711002_P01_ELECTRICAL-POWER-UNIT-FRONT-PLATE_CAD (Autodesk Fusion 360 design; units mm, degrees)
description: ELECTRICAL - POWER UNIT - FRONT PLATE | Điện - hộp nguồn - mặt trước | P01
part number: 711002
Autodesk Fusion 360 part; units mm, degrees
sketch "OUTLINE AND CUT-OUTS - FRONT" plane through (0, 0, 0) normal (0, 0, 1) x (1, 0, 0) in component "711002 ELECTRICAL - POWER UNIT - FRONT PLATE"
  line L0 (0, 0) -> (320, 0)
  line L1 (320, 0) -> (320, 284)
  line L2 (320, 284) -> (0, 284)
  line L3 (0, 284) -> (0, 0)
  line L4 (65.2, 158.5) -> (98.8, 158.5)
  line L5 (98.8, 158.5) -> (98.8, 225.5)
  line L6 (98.8, 225.5) -> (65.2, 225.5)
  line L7 (65.2, 225.5) -> (65.2, 158.5)
  circle A0 centre (82, 143.6) radius 1.9
  line L8 (167.55, 182.3) -> (182.45, 182.3)
  line L9 (182.45, 182.3) -> (182.45, 201.7)
  line L10 (182.45, 201.7) -> (167.55, 201.7)
  line L11 (167.55, 201.7) -> (167.55, 182.3)
  circle A1 centre (82, 240.4) radius 1.9
  line L12 (191.55, 182.3) -> (206.45, 182.3)
  line L13 (206.45, 182.3) -> (206.45, 201.7)
  line L14 (206.45, 201.7) -> (191.55, 201.7)
  line L15 (191.55, 201.7) -> (191.55, 182.3)
  line L16 (247.5, 169.5) -> (266.5, 169.5)
  line L17 (266.5, 169.5) -> (266.5, 214.5)
  line L18 (266.5, 214.5) -> (247.5, 214.5)
  line L19 (247.5, 214.5) -> (247.5, 169.5)
  line L20 (40, 35) -> (80, 35)
  line L21 (80, 35) -> (80, 39)
  line L22 (80, 39) -> (40, 39)
  line L23 (40, 39) -> (40, 35)
  line L24 (90, 35) -> (130, 35)
  line L25 (130, 35) -> (130, 39)
  line L26 (130, 39) -> (90, 39)
  line L27 (90, 39) -> (90, 35)
  line L28 (140, 35) -> (180, 35)
  line L29 (180, 35) -> (180, 39)
  line L30 (180, 39) -> (140, 39)
  line L31 (140, 39) -> (140, 35)
  line L32 (190, 35) -> (230, 35)
  line L33 (230, 35) -> (230, 39)
  line L34 (230, 39) -> (190, 39)
  line L35 (190, 39) -> (190, 35)
  line L36 (240, 35) -> (280, 35)
  line L37 (280, 35) -> (280, 39)
  line L38 (280, 39) -> (240, 39)
  line L39 (240, 39) -> (240, 35)
  line L40 (40, 130) -> (80, 130)
  line L41 (80, 130) -> (80, 134)
  line L42 (80, 134) -> (40, 134)
  line L43 (40, 134) -> (40, 130)
  line L44 (90, 130) -> (130, 130)
  line L45 (130, 130) -> (130, 134)
  line L46 (130, 134) -> (90, 134)
  line L47 (90, 134) -> (90, 130)
  line L48 (140, 130) -> (180, 130)
  line L49 (180, 130) -> (180, 134)
  line L50 (180, 134) -> (140, 134)
  line L51 (140, 134) -> (140, 130)
  line L52 (190, 130) -> (230, 130)
  line L53 (230, 130) -> (230, 134)
  line L54 (230, 134) -> (190, 134)
  line L55 (190, 134) -> (190, 130)
  line L56 (240, 130) -> (280, 130)
  line L57 (280, 130) -> (280, 134)
  line L58 (280, 134) -> (240, 134)
  line L59 (240, 134) -> (240, 130)
  circle A2 centre (42, 22) radius 2.25
  circle A3 centre (278, 22) radius 2.25
  circle A4 centre (42, 262) radius 2.25
  circle A5 centre (278, 262) radius 2.25
  dimension "d314" = 320
  dimension "d315" = 284
  dimension "d316" = 33.6
  dimension "d317" = 67
  dimension "d318" = 65.2
  dimension "d319" = 158.5
  dimension "d320" = 3.8
  dimension "d321" = 82
  dimension "d322" = 143.6
  dimension "d323" = 14.9
  dimension "d324" = 19.4
  dimension "d325" = 167.55
  dimension "d326" = 182.3
  dimension "d327" = 3.8
  dimension "d328" = 82
  dimension "d329" = 240.4
  dimension "d330" = 14.9
  dimension "d331" = 19.4
  dimension "d332" = 191.55
  dimension "d333" = 182.3
  dimension "d334" = 19
  dimension "d335" = 45
  dimension "d336" = 247.5
  dimension "d337" = 169.5
  dimension "d338" = 40
  dimension "d339" = 4
  dimension "d340" = 40
  dimension "d341" = 35
  dimension "d342" = 40
  dimension "d343" = 4
  dimension "d344" = 90
  dimension "d345" = 35
  dimension "d346" = 40
  dimension "d347" = 4
  dimension "d348" = 140
  dimension "d349" = 35
  dimension "d350" = 40
  dimension "d351" = 4
  dimension "d352" = 190
  dimension "d353" = 35
  dimension "d354" = 40
  dimension "d355" = 4
  dimension "d356" = 240
  dimension "d357" = 35
  dimension "d358" = 40
  dimension "d359" = 4
  dimension "d360" = 40
  dimension "d361" = 130
  dimension "d362" = 40
  dimension "d363" = 4
  dimension "d364" = 90
  dimension "d365" = 130
  dimension "d366" = 40
  dimension "d367" = 4
  dimension "d368" = 140
  dimension "d369" = 130
  dimension "d370" = 40
  dimension "d371" = 4
  dimension "d372" = 190
  dimension "d373" = 130
  dimension "d374" = 40
  dimension "d375" = 4
  dimension "d376" = 240
  dimension "d377" = 130
  dimension "d378" = 4.5
  dimension "d379" = 42
  dimension "d380" = 22
  dimension "d381" = 4.5
  dimension "d382" = 278
  dimension "d383" = 22
  dimension "d384" = 4.5
  dimension "d385" = 42
  dimension "d386" = 262
  dimension "d387" = 4.5
  dimension "d388" = 278
  dimension "d389" = 262
  constraint horizontal L0
  constraint vertical L1
  constraint horizontal L2
  constraint vertical L3
  constraint vertical L0.start L3.end
  constraint horizontal L0.start L3.end
  constraint horizontal L4
  constraint vertical L5
  constraint horizontal L6
  constraint vertical L7
  constraint horizontal L8
  constraint vertical L9
  constraint horizontal L10
  constraint vertical L11
  constraint horizontal L12
  constraint vertical L13
  constraint horizontal L14
  constraint vertical L15
  constraint horizontal L16
  constraint vertical L17
  constraint horizontal L18
  constraint vertical L19
  constraint horizontal L20
  constraint vertical L21
  constraint horizontal L22
  constraint vertical L23
  constraint horizontal L24
  constraint vertical L25
  constraint horizontal L26
  constraint vertical L27
  constraint horizontal L28
  constraint vertical L29
  constraint horizontal L30
  constraint vertical L31
  constraint horizontal L32
  constraint vertical L33
  constraint horizontal L34
  constraint vertical L35
  constraint horizontal L36
  constraint vertical L37
  constraint horizontal L38
  constraint vertical L39
  constraint horizontal L40
  constraint vertical L41
  constraint horizontal L42
  constraint vertical L43
  constraint horizontal L44
  constraint vertical L45
  constraint horizontal L46
  constraint vertical L47
  constraint horizontal L48
  constraint vertical L49
  constraint horizontal L50
  constraint vertical L51
  constraint horizontal L52
  constraint vertical L53
  constraint horizontal L54
  constraint vertical L55
  constraint horizontal L56
  constraint vertical L57
  constraint horizontal L58
  constraint vertical L59
  measures "d314" horizontal distance of L0.start L0.end
  measures "d315" vertical distance of L0.start L2.end
  measures "d316" horizontal distance of L4.start L4.end
  measures "d317" vertical distance of L4.start L6.end
  measures "d318" horizontal distance of L0.start L4.start
  measures "d319" vertical distance of L0.start L4.start
  measures "d320" diameter of A0
  measures "d321" horizontal distance of L0.start A0.centre
  measures "d322" vertical distance of L0.start A0.centre
  measures "d323" horizontal distance of L8.start L8.end
  measures "d324" vertical distance of L8.start L10.end
  measures "d325" horizontal distance of L0.start L8.start
  measures "d326" vertical distance of L0.start L8.start
  measures "d327" diameter of A1
  measures "d328" horizontal distance of L0.start A1.centre
  measures "d329" vertical distance of L0.start A1.centre
  measures "d330" horizontal distance of L12.start L12.end
  measures "d331" vertical distance of L12.start L14.end
  measures "d332" horizontal distance of L0.start L12.start
  measures "d333" vertical distance of L0.start L12.start
  measures "d334" horizontal distance of L16.start L16.end
  measures "d335" vertical distance of L16.start L18.end
  measures "d336" horizontal distance of L0.start L16.start
  measures "d337" vertical distance of L0.start L16.start
  measures "d338" horizontal distance of L20.start L20.end
  measures "d339" vertical distance of L20.start L22.end
  measures "d340" horizontal distance of L0.start L20.start
  measures "d341" vertical distance of L0.start L20.start
  measures "d342" horizontal distance of L24.start L24.end
  measures "d343" vertical distance of L24.start L26.end
  measures "d344" horizontal distance of L0.start L24.start
  measures "d345" vertical distance of L0.start L24.start
  measures "d346" horizontal distance of L28.start L28.end
  measures "d347" vertical distance of L28.start L30.end
  measures "d348" horizontal distance of L0.start L28.start
  measures "d349" vertical distance of L0.start L28.start
  measures "d350" horizontal distance of L32.start L32.end
  measures "d351" vertical distance of L32.start L34.end
  measures "d352" horizontal distance of L0.start L32.start
  measures "d353" vertical distance of L0.start L32.start
  measures "d354" horizontal distance of L36.start L36.end
  measures "d355" vertical distance of L36.start L38.end
  measures "d356" horizontal distance of L0.start L36.start
  measures "d357" vertical distance of L0.start L36.start
  measures "d358" horizontal distance of L40.start L40.end
  measures "d359" vertical distance of L40.start L42.end
  measures "d360" horizontal distance of L0.start L40.start
  measures "d361" vertical distance of L0.start L40.start
  measures "d362" horizontal distance of L44.start L44.end
  measures "d363" vertical distance of L44.start L46.end
  measures "d364" horizontal distance of L0.start L44.start
  measures "d365" vertical distance of L0.start L44.start
  measures "d366" horizontal distance of L48.start L48.end
  measures "d367" vertical distance of L48.start L50.end
  measures "d368" horizontal distance of L0.start L48.start
  measures "d369" vertical distance of L0.start L48.start
  measures "d370" horizontal distance of L52.start L52.end
  measures "d371" vertical distance of L52.start L54.end
  measures "d372" horizontal distance of L0.start L52.start
  measures "d373" vertical distance of L0.start L52.start
  measures "d374" horizontal distance of L56.start L56.end
  measures "d375" vertical distance of L56.start L58.end
  measures "d376" horizontal distance of L0.start L56.start
  measures "d377" vertical distance of L0.start L56.start
  measures "d378" diameter of A2
  measures "d379" horizontal distance of L0.start A2.centre
  measures "d380" vertical distance of L0.start A2.centre
  measures "d381" diameter of A3
  measures "d382" horizontal distance of L0.start A3.centre
  measures "d383" vertical distance of L0.start A3.centre
  measures "d384" diameter of A4
  measures "d385" horizontal distance of L0.start A4.centre
  measures "d386" vertical distance of L0.start A4.centre
  measures "d387" diameter of A5
  measures "d388" horizontal distance of L0.start A5.centre
  measures "d389" vertical distance of L0.start A5.centre
extrude "EXTRUDE - PLATE FRONT" add sketch "OUTLINE AND CUT-OUTS - FRONT" along normal blind 1.5 in component "711002 ELECTRICAL - POWER UNIT - FRONT PLATE"
component "711002 ELECTRICAL - POWER UNIT - FRONT PLATE" placed x (1, 0, 0) y (0, 1, 0) z (0, 0, 1) at (0, 0, 0)
equation "t = 1.5 mm" comment "PROPOSED: 5052-H32 aluminium 1.5 mm, black anodised AA20 (D-67)"
equation "w = 320.0 mm" comment "CALCULATION: the unit's width 296 + 2 x (4 mm clear + 8 mm over the felt): the plate covers the cut-out's felt edge all round (route model pu_w, pu_clr, plate_ov)"
equation "h = 284.0 mm" comment "CALCULATION: the unit's height 260 + 2 x (4 + 8) (route model pu_h, pu_clr, plate_ov)"
equation "box_a = 73 mm" comment "HOLD: opening for an 86-type back box mouth; the UTEN code and its box set it (H-ELE-04)"
equation "box_zc = edge_off + 195 mm" comment "ASSUMPTION: 86-plate openings' centre height: 195 above the unit's bottom (Z 1065, the unit's centre + 65)"
equation "box_x1 = edge_off + 70 mm" comment "ASSUMPTION: socket opening centre: 70 from the unit's left side (the box mouth 11.5 mm clear of the body's 22 mm left lip)"
equation "box_x2 = edge_off + 175 mm" comment "ASSUMPTION: LAN opening centre: 175 from the unit's left side (32 mm between the two box mouths)"
equation "din_w = 19 mm" comment "SOURCE: breaker window: 1 module + 1 (Eaton FAZ-NA is 17.7 mm per pole, D-133)"
equation "din_h = 45 mm" comment "SOURCE: DIN 43880 front height 45 mm"
equation "din_x = edge_off + 245 mm" comment "ASSUMPTION: breaker window centre: 245 from the unit's left side, 41 mm from the keystone openings, 19.5 mm clear of the body's 22 mm right lip"
equation "din_zc = dev_zc" comment "ASSUMPTION: breaker window centre height, level with the devices"
equation "vent_l = 40 mm" comment "ASSUMPTION: vent slot length"
equation "vent_w = 4 mm" comment "ASSUMPTION: vent slot width"
equation "vent_n = 5" comment "ASSUMPTION: vent slots per row (two rows: bottom and top)"
equation "vent_p = 50 mm" comment "ASSUMPTION: vent slot pitch"
equation "vent_z1 = edge_off + 25 mm" comment "ASSUMPTION: bottom vent row centre: 25 above the unit's bottom, just above the body's 22 mm lip"
equation "vent_z2 = edge_off + 120 mm" comment "ASSUMPTION: top vent row centre: 120 above the unit's bottom, 4.7 mm under the GFCI receptacle's strap (D-133)"
equation "screw_d = 4.5 mm" comment "ASSUMPTION: M4 screw clearance hole"
equation "screw_x = edge_off + 30 mm" comment "CALCULATION: screw centre: on the body's clinch nuts, 30 from the unit's sides (clinch_x)"
equation "screw_y = edge_off + 10 mm" comment "CALCULATION: screw centre: on the body's clinch nuts, 10 from the unit's top and bottom (clinch_y; 22 from the plate's edge, C09)"
equation "edge_off = 12.0 mm" comment "CALCULATION: the unit's edge from the plate's edge: 4 mm clear + 8 mm over the felt; every opening is placed from the unit's edge"
equation "dev_zc = edge_off + 180 mm" comment "ASSUMPTION: the devices' centre height: 180 above the unit's bottom; the GFCI receptacle's 106.7 mm strap runs 126.7 to 233.3, 4.7 mm clear of the top vent row and of the body's 22 mm top lip (D-133)"
equation "gfci_w = 33.6 mm" comment "HOLD: GFCI receptacle's decorator opening width: the face 33.3 (1.31 in) + 0.3; the picked receptacle's drawing sets it (D-133)"
equation "gfci_h = 67 mm" comment "HOLD: decorator opening height: the face 66.7 (2.625 in) + 0.3 (D-133)"
equation "gfci_x = edge_off + 70 mm" comment "ASSUMPTION: GFCI opening centre: 70 from the unit's left side; its 43.7 mm strap is 26 mm clear of the body's 22 mm left lip"
equation "gfci_sp = 96.8 mm" comment "SOURCE: the two 6-32 plate screws' spacing on a decorator device's strap: 3-13/16 in"
equation "gfci_sd = 3.8 mm" comment "ASSUMPTION: 6-32 clearance hole (normal fit)"
equation "ks_w = 14.9 mm" comment "HOLD: keystone jack opening width (the common 0.585 x 0.760 in snap-in opening; the picked jack sets it, D-133)"
equation "ks_h = 19.4 mm" comment "HOLD: keystone jack opening height"
equation "ks_x = edge_off + 175 mm" comment "ASSUMPTION: LAN: the two keystone openings' centre, 175 from the unit's left side"
equation "ks_p = 24 mm" comment "ASSUMPTION: the two keystone openings' pitch: side by side, the jacks' 16.5 mm bodies 7.5 mm apart"
equation "d314 = ( w ) - ( 0 mm )"
equation "d315 = ( h ) - ( 0 mm )"
equation "d316 = ( gfci_x + gfci_w / 2 ) - ( gfci_x - gfci_w / 2 )"
equation "d317 = ( dev_zc + gfci_h / 2 ) - ( dev_zc - gfci_h / 2 )"
equation "d318 = abs(gfci_x - gfci_w / 2)"
equation "d319 = abs(dev_zc - gfci_h / 2)"
equation "d320 = gfci_sd"
equation "d321 = abs(gfci_x)"
equation "d322 = abs(dev_zc - gfci_sp / 2)"
equation "d323 = ( ( ks_x - ks_p / 2 ) + ks_w / 2 ) - ( ( ks_x - ks_p / 2 ) - ks_w / 2 )"
equation "d324 = ( dev_zc + ks_h / 2 ) - ( dev_zc - ks_h / 2 )"
equation "d325 = abs(( ks_x - ks_p / 2 ) - ks_w / 2)"
equation "d326 = abs(dev_zc - ks_h / 2)"
equation "d327 = gfci_sd"
equation "d328 = abs(gfci_x)"
equation "d329 = abs(dev_zc + gfci_sp / 2)"
equation "d330 = ( ( ks_x + ks_p / 2 ) + ks_w / 2 ) - ( ( ks_x + ks_p / 2 ) - ks_w / 2 )"
equation "d331 = ( dev_zc + ks_h / 2 ) - ( dev_zc - ks_h / 2 )"
equation "d332 = abs(( ks_x + ks_p / 2 ) - ks_w / 2)"
equation "d333 = abs(dev_zc - ks_h / 2)"
equation "d334 = ( din_x + din_w / 2 ) - ( din_x - din_w / 2 )"
equation "d335 = ( din_zc + din_h / 2 ) - ( din_zc - din_h / 2 )"
equation "d336 = abs(din_x - din_w / 2)"
equation "d337 = abs(din_zc - din_h / 2)"
equation "d338 = ( ( w / 2 + ( 0 - ( vent_n - 1 ) / 2 ) * vent_p ) + vent_l / 2 ) - ( ( w / 2 + ( 0 - ( vent_n - 1 ) / 2 ) * vent_p ) - vent_l / 2 )"
equation "d339 = ( ( vent_z1 ) + vent_w / 2 ) - ( ( vent_z1 ) - vent_w / 2 )"
equation "d340 = abs(( w / 2 + ( 0 - ( vent_n - 1 ) / 2 ) * vent_p ) - vent_l / 2)"
equation "d341 = abs(( vent_z1 ) - vent_w / 2)"
equation "d342 = ( ( w / 2 + ( 1 - ( vent_n - 1 ) / 2 ) * vent_p ) + vent_l / 2 ) - ( ( w / 2 + ( 1 - ( vent_n - 1 ) / 2 ) * vent_p ) - vent_l / 2 )"
equation "d343 = ( ( vent_z1 ) + vent_w / 2 ) - ( ( vent_z1 ) - vent_w / 2 )"
equation "d344 = abs(( w / 2 + ( 1 - ( vent_n - 1 ) / 2 ) * vent_p ) - vent_l / 2)"
equation "d345 = abs(( vent_z1 ) - vent_w / 2)"
equation "d346 = ( ( w / 2 + ( 2 - ( vent_n - 1 ) / 2 ) * vent_p ) + vent_l / 2 ) - ( ( w / 2 + ( 2 - ( vent_n - 1 ) / 2 ) * vent_p ) - vent_l / 2 )"
equation "d347 = ( ( vent_z1 ) + vent_w / 2 ) - ( ( vent_z1 ) - vent_w / 2 )"
equation "d348 = abs(( w / 2 + ( 2 - ( vent_n - 1 ) / 2 ) * vent_p ) - vent_l / 2)"
equation "d349 = abs(( vent_z1 ) - vent_w / 2)"
equation "d350 = ( ( w / 2 + ( 3 - ( vent_n - 1 ) / 2 ) * vent_p ) + vent_l / 2 ) - ( ( w / 2 + ( 3 - ( vent_n - 1 ) / 2 ) * vent_p ) - vent_l / 2 )"
equation "d351 = ( ( vent_z1 ) + vent_w / 2 ) - ( ( vent_z1 ) - vent_w / 2 )"
equation "d352 = abs(( w / 2 + ( 3 - ( vent_n - 1 ) / 2 ) * vent_p ) - vent_l / 2)"
equation "d353 = abs(( vent_z1 ) - vent_w / 2)"
equation "d354 = ( ( w / 2 + ( 4 - ( vent_n - 1 ) / 2 ) * vent_p ) + vent_l / 2 ) - ( ( w / 2 + ( 4 - ( vent_n - 1 ) / 2 ) * vent_p ) - vent_l / 2 )"
equation "d355 = ( ( vent_z1 ) + vent_w / 2 ) - ( ( vent_z1 ) - vent_w / 2 )"
equation "d356 = abs(( w / 2 + ( 4 - ( vent_n - 1 ) / 2 ) * vent_p ) - vent_l / 2)"
equation "d357 = abs(( vent_z1 ) - vent_w / 2)"
equation "d358 = ( ( w / 2 + ( 0 - ( vent_n - 1 ) / 2 ) * vent_p ) + vent_l / 2 ) - ( ( w / 2 + ( 0 - ( vent_n - 1 ) / 2 ) * vent_p ) - vent_l / 2 )"
equation "d359 = ( ( vent_z2 ) + vent_w / 2 ) - ( ( vent_z2 ) - vent_w / 2 )"
equation "d360 = abs(( w / 2 + ( 0 - ( vent_n - 1 ) / 2 ) * vent_p ) - vent_l / 2)"
equation "d361 = abs(( vent_z2 ) - vent_w / 2)"
equation "d362 = ( ( w / 2 + ( 1 - ( vent_n - 1 ) / 2 ) * vent_p ) + vent_l / 2 ) - ( ( w / 2 + ( 1 - ( vent_n - 1 ) / 2 ) * vent_p ) - vent_l / 2 )"
equation "d363 = ( ( vent_z2 ) + vent_w / 2 ) - ( ( vent_z2 ) - vent_w / 2 )"
equation "d364 = abs(( w / 2 + ( 1 - ( vent_n - 1 ) / 2 ) * vent_p ) - vent_l / 2)"
equation "d365 = abs(( vent_z2 ) - vent_w / 2)"
equation "d366 = ( ( w / 2 + ( 2 - ( vent_n - 1 ) / 2 ) * vent_p ) + vent_l / 2 ) - ( ( w / 2 + ( 2 - ( vent_n - 1 ) / 2 ) * vent_p ) - vent_l / 2 )"
equation "d367 = ( ( vent_z2 ) + vent_w / 2 ) - ( ( vent_z2 ) - vent_w / 2 )"
equation "d368 = abs(( w / 2 + ( 2 - ( vent_n - 1 ) / 2 ) * vent_p ) - vent_l / 2)"
equation "d369 = abs(( vent_z2 ) - vent_w / 2)"
equation "d370 = ( ( w / 2 + ( 3 - ( vent_n - 1 ) / 2 ) * vent_p ) + vent_l / 2 ) - ( ( w / 2 + ( 3 - ( vent_n - 1 ) / 2 ) * vent_p ) - vent_l / 2 )"
equation "d371 = ( ( vent_z2 ) + vent_w / 2 ) - ( ( vent_z2 ) - vent_w / 2 )"
equation "d372 = abs(( w / 2 + ( 3 - ( vent_n - 1 ) / 2 ) * vent_p ) - vent_l / 2)"
equation "d373 = abs(( vent_z2 ) - vent_w / 2)"
equation "d374 = ( ( w / 2 + ( 4 - ( vent_n - 1 ) / 2 ) * vent_p ) + vent_l / 2 ) - ( ( w / 2 + ( 4 - ( vent_n - 1 ) / 2 ) * vent_p ) - vent_l / 2 )"
equation "d375 = ( ( vent_z2 ) + vent_w / 2 ) - ( ( vent_z2 ) - vent_w / 2 )"
equation "d376 = abs(( w / 2 + ( 4 - ( vent_n - 1 ) / 2 ) * vent_p ) - vent_l / 2)"
equation "d377 = abs(( vent_z2 ) - vent_w / 2)"
equation "d378 = screw_d"
equation "d379 = abs(screw_x)"
equation "d380 = abs(screw_y)"
equation "d381 = screw_d"
equation "d382 = abs(w - screw_x)"
equation "d383 = abs(screw_y)"
equation "d384 = screw_d"
equation "d385 = abs(screw_x)"
equation "d386 = abs(h - screw_y)"
equation "d387 = screw_d"
equation "d388 = abs(w - screw_x)"
equation "d389 = abs(h - screw_y)"
equation "d390 = t"
named bodies: "ELECTRICAL - POWER UNIT - FRONT PLATE"
